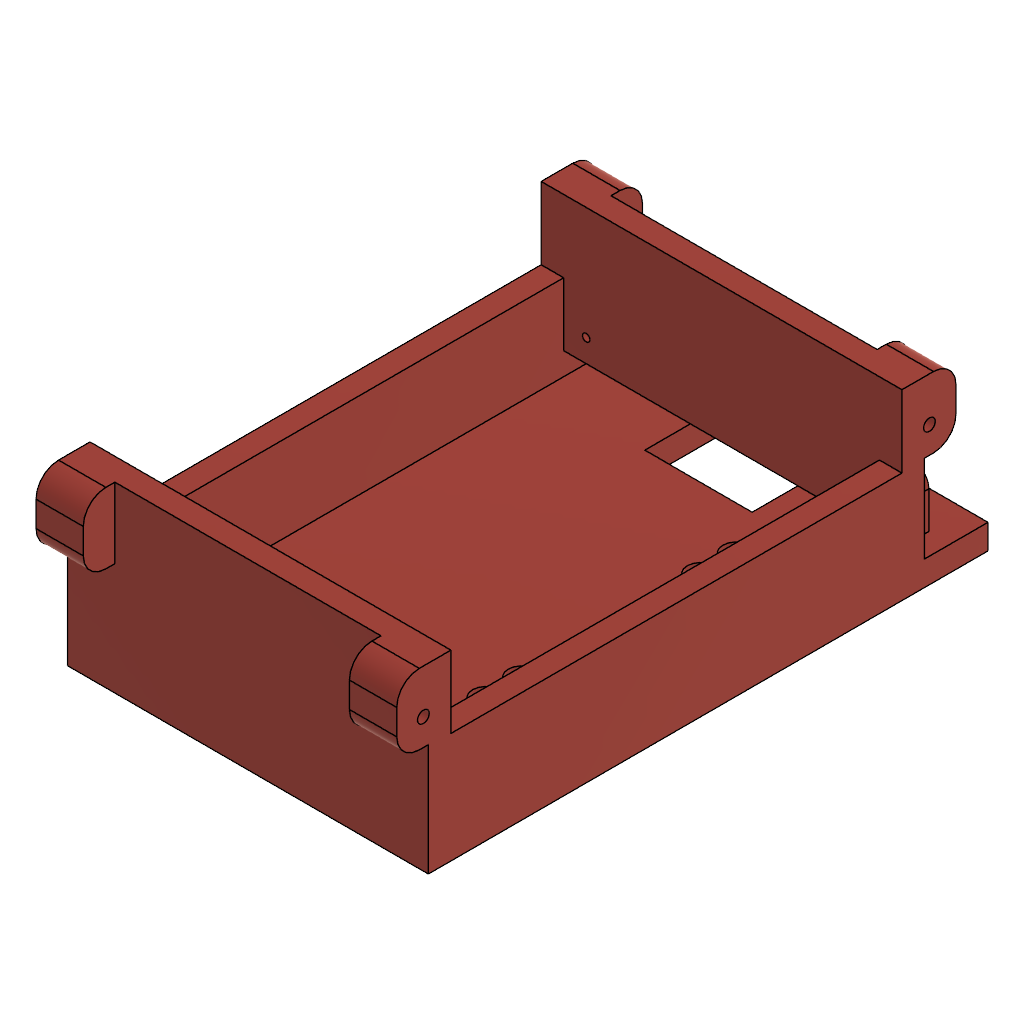
Card_Drop_Box (Autodesk Fusion 360 design; units mm, degrees)
part number: 2026-11-03-15-18-22-422
Autodesk Fusion 360 part; units mm, degrees
sketch "Çizim1" plane through (0, 0, 0) normal (0, 0, 1) x (1, 0, 0)
  line L0 (35, 50) -> (-35, 50)
  line L1 (-35, 50) -> (-35, -50)
  line L2 (-35, -50) -> (35, -50)
  line L3 (35, -50) -> (35, 50)
  line L4 (35, 50) -> (-35, -50) construction
  line L5 (-35, 50) -> (35, -50) construction
  line L6 (-40, -55) -> (40, -55)
  line L7 (40, -55) -> (40, 55)
  line L8 (40, 55) -> (-40, 55)
  line L9 (-40, 55) -> (-40, -55)
  dimension "d1" = 70
  dimension "d2" = 100
  dimension "d3" = 5
  constraint horizontal L0
  constraint perpendicular L0 L1
  constraint parallel L0 L2
  constraint parallel L1 L3
  constraint coincident L4 origin
  constraint coincident L5 origin
  measures "d1" distance of L1.end L2.end
  measures "d2" distance of L0.end L1.end
extrude "Ekstrüzyon1" add sketch "Çizim1" against normal blind 5 contours L0 L1 L2 L3 | L6 L7 L8 L9 makes body 1
extrude "Ekstrüzyon2" add sketch "Çizim1" along normal blind 35 bodies 1
sketch "Çizim2" plane through (40, 0, 0) normal (1, 0, 0) x (0, 1, 0)
  line L0 (-55, 35) -> (-55, -5)
  line L1 (-55, -5) -> (55, -5)
  line L2 (55, -5) -> (55, 35)
  line L3 (55, 35) -> (-55, 35)
  line L4 (0, 35) -> (-57, 35)
  line L5 (0, 35) -> (62, 35)
  line L6 (-56.1, 35) -> (-56.1, 25.25)
  circle A0 centre (-56.1, 25.25) radius 1.3
  circle A1 centre (-56.1, 25.25) radius 5.9
  line L7 (-62, 30) -> (-62, 25.25)
  line L8 (-62, 25.25) -> (-62, 14)
  line L9 (-56.1, 25.25) -> (-56.1, 19.35)
  line L10 (-56.1, 19.35) -> (-62, 19.35)
  line L11 (-56.1, 19.35) -> (-55, 19.35)
  arc A2 (-57, 35) -> (-62, 30) centre (-57, 30) ccw
  point P0 (-62, 35)
  dimension "d8" = 62
  dimension "d9" = 62
  dimension "d10" = 9.75
  dimension "d11" = 5.9
  dimension "d12" = 2.6
  dimension "d13" = 5
  constraint midpoint L3 L4.start
  constraint parallel L3 L4
  constraint parallel L3 L5
  constraint coincident L4 L6.start
  constraint perpendicular L4 L6
  constraint coincident L6.end A0.centre
  constraint concentric A0 A1
  constraint coincident A1 L7.end
  constraint tangent A1 L7
  constraint perpendicular L4 L7
  constraint tangent A1 L8
  constraint coincident A1 L9.end
  constraint parallel L6 L9
  constraint tangent A1 L10
  constraint coincident L0 L11.end
  constraint tangent A1 L11
  constraint coincident P0 L4
  constraint coincident P0 L7
  constraint tangent L4 A2
  constraint tangent L7 A2
  measures "d8" distance of L4.start P0
  measures "d9" distance of L4.start L5.end
  measures "d10" distance of L6.start L6.end
  measures "d11" distance of P0 L6
  measures "d12" diameter of A0
  measures "d13" radius of A2
extrude "Ekstrüzyon3" add sketch "Çizim2" against normal blind 5.5 contours L0 A1 L11 | L0 A0 A1 L9 | A1 L8 L10 | L6 A0 A1 L9 | L4 L6 A1 L7 A2 | L0 L6 A0 A1 | L0 L4 L6 A1 bodies 1
extrude "Ekstrüzyon4" cut sketch "Çizim2" against normal blind 7 contours L0 A0 bodies 1
mirror "Ayna1" about plane through (0, 0, 0) normal (0, 1, 0) of "Ekstrüzyon3", "Ekstrüzyon4"
extrude "Ekstrüzyon5" add 2 faces at (34.5, -60.4655, 24.8348) (34.5, 60.4655, 24.8348) along direction (-1, 0, 0) blind 5 on bodies 1 bodies 1
sketch "Çizim3" plane through (29.5, 0, 0) normal (-1, 0, 0) x (0, -1, 0)
  line L0 (57, 35) -> (55, 35)
  line L1 (55, 35) -> (55, 25.9428)
  arc A0 (55, 24.5572) -> (55, 25.9428) centre (56.1, 25.25) ccw
  line L2 (55, 24.5572) -> (55, 19.35)
  line L3 (55, 19.35) -> (62, 19.35)
  line L4 (62, 19.35) -> (62, 30)
  arc A1 (62, 30) -> (57, 35) centre (57, 30) ccw
  circle A2 centre (56.1, 25.25) radius 1.3
  constraint concentric A0 A2
extrude "Ekstrüzyon6" add sketch "Çizim3" against normal blind 3.5 contours A0 A2 bodies 1
mirror "Ayna2" about plane through (0, 0, 0) normal (0, 1, 0) of "Ekstrüzyon6"
mirror "Ayna3" about plane through (0, 0, 0) normal (1, 0, 0) of "Ekstrüzyon3", "Ekstrüzyon4", "Ayna1", "Ekstrüzyon5", "Ekstrüzyon6", "Ayna2"
sketch "Çizim4" plane through (-40, 0, 0) normal (-1, 0, 0) x (0, -1, 0)
  circle A0 centre (56.1, 25.25) radius 1.3
  circle A1 centre (-56.1, 25.25) radius 1.3
  line L0 (-55, 19.35) -> (-55, -5)
  line L1 (-55, -5) -> (55, -5)
  line L2 (55, -5) -> (55, 19.35)
  line L3 (62, 19.35) -> (62, 30)
  arc A2 (62, 30) -> (57, 35) centre (57, 30) ccw
  line L4 (57, 35) -> (-57, 35)
  arc A3 (-57, 35) -> (-62, 30) centre (-57, 30) ccw
  line L5 (-62, 30) -> (-62, 19.35)
  line L6 (0, 35) -> (0, 20)
  line L7 (0, 20) -> (50, 20)
  line L8 (50, 20) -> (50, 23)
  line L9 (50, 23) -> (0, 23)
  line L10 (0, 23) -> (0, 20)
  line L11 (0, 20) -> (-50, 20)
  line L12 (-50, 20) -> (-50, 23)
  line L13 (-50, 23) -> (0, 23)
  line L14 (0, 23) -> (0, 20)
  line L15 (0, 35) -> (0, 32)
  line L16 (55, 19.35) -> (62, 19.35)
  line L17 (-62, 19.35) -> (-55, 19.35)
  dimension "d34" = 15
  dimension "d35" = 50
  dimension "d36" = 3
  dimension "d37" = 3
  dimension "d40" = 50
  constraint midpoint L4 L6.start
  constraint perpendicular L4 L6
  constraint horizontal L7
  constraint vertical L8
  constraint horizontal L9
  constraint vertical L10
  constraint horizontal L11
  constraint vertical L12
  constraint horizontal L13
  constraint vertical L14
  constraint coincident L6 L15.end
  measures "d34" distance of L6.start L6.end
  measures "d35" distance of L6.end L7.end
  measures "d36" distance of L6.end L9.end
  measures "d37" distance of L6.end L9.end
  measures "d40" distance of L12.end L9.end
extrude "Ekstrüzyon7" cut sketch "Çizim4" against normal blind 80 contours L6 L7 L8 L9 L10 L14 | L6 L10 L11 L12 L13 L14 bodies 1
extrude "Ekstrüzyon8" cut 4 faces at (38.3333, -16.6667, 23) (36.6667, 33.3333, 23) (-38.3333, -33.3333, 23) (-36.6667, 16.6667, 23) along direction (0, 0, 1) blind 12 on bodies 1 bodies 1
extrude "Ekstrüzyon9" add 1 faces at (-13.3333, -18.3333, -5) along direction (0, 0, -1) blind 0.5 on bodies 1 bodies 1
sketch "Çizim5" plane through (0, 0, -5.5) normal (0, 0, -1) x (1, 0, 0)
  line L0 (-40, 55) -> (-40, -55)
  line L1 (-40, -55) -> (40, -55)
  line L2 (40, -55) -> (40, 55)
  line L3 (40, 55) -> (-40, 55)
  line L4 (-35, -50) -> (35, -50)
  line L5 (35, -50) -> (35, 50)
  line L6 (35, 50) -> (-35, 50)
  line L7 (-35, 50) -> (-35, -50)
  line L8 (0, 50) -> (0, 29.8)
  line L9 (0, 29.8) -> (-11.9, 29.8)
  line L10 (0, 29.8) -> (11.9, 29.8)
  line L11 (-11.9, 29.8) -> (11.9, 29.8)
  line L12 (11.9, 29.8) -> (11.9, 50)
  line L13 (11.9, 50) -> (-11.9, 50)
  line L14 (-11.9, 50) -> (-11.9, 29.8)
  line L15 (11.9, 50) -> (11.9, 39.9)
  line L16 (11.9, 29.8) -> (18, 29.8)
  line L17 (18, 29.8) -> (18, 20.2)
  line L18 (18, 20.2) -> (18, 12.3)
  circle A0 centre (18, 20.2) radius 1.3
  circle A1 centre (18, 12.3) radius 1.3
  dimension "d45" = -5
  dimension "d46" = 20.2
  dimension "d47" = 11.9
  dimension "d48" = 11.9
  dimension "d49" = 23.8
  dimension "d50" = 6.1
  dimension "d51" = 9.6
  dimension "d52" = 7.9
  dimension "d53" = 2.6
  dimension "d54" = 2.6
  constraint midpoint L6 L8.start
  constraint perpendicular L6 L8
  constraint perpendicular L8 L9
  constraint perpendicular L8 L10
  constraint horizontal L11
  constraint vertical L12
  constraint horizontal L13
  constraint vertical L14
  constraint midpoint L12 L15.end
  constraint perpendicular L12 L16
  constraint perpendicular L16 L17
  constraint perpendicular L11 L18
  constraint coincident L17.end L18.start
  constraint coincident L18.end A1.centre
  measures "d46" distance of L8.start L8.end
  measures "d47" distance of L8.end L9.end
  measures "d48" distance of L8.end L10.end
  measures "d49" distance of L9.end L10.end
  measures "d50" distance of L10.end L16.end
  measures "d51" distance of L16.end L17.end
  measures "d52" distance of L17.end L18.end
  measures "d53" diameter of A0
  measures "d54" diameter of A1
extrude "Ekstrüzyon10" cut sketch "Çizim5" against normal blind 5.5 contours L6 L8 L9 L11 L13 L14 | L6 L8 L10 L11 L12 L13 L15 | L17 L18 A0 | L17 L18 A0 | A1 bodies 1
sketch "Çizim6" plane through (0, 50, 0) normal (0, -1, 0) x (1, 0, 0)
  line L0 (-35, 20) -> (-35, 0)
  line L1 (-35, 0) -> (35, 0)
  line L2 (35, 0) -> (35, 20)
  line L3 (35, 20) -> (40, 20)
  line L4 (40, 20) -> (40, 35)
  line L5 (40, 35) -> (-40, 35)
  line L6 (-40, 35) -> (-40, 20)
  line L7 (-40, 20) -> (-35, 20)
  line L8 (-35, 0) -> (35, 0)
  line L9 (35, 0) -> (35, 5)
  line L10 (35, 5) -> (-35, 5)
  line L11 (-35, 5) -> (-35, 0)
  dimension "d57" = 5
  constraint horizontal L8
  constraint vertical L9
  constraint horizontal L10
  constraint vertical L11
  constraint coincident L0.end L1.start
  measures "d57" distance of L0.end L10.end
extrude "Ekstrüzyon11" cut sketch "Çizim6" against normal blind 5 contours L0 L1 L2 L8 L9 L10 L11 bodies 1
sketch "Çizim7" plane through (0, 55, 0) normal (0, 1, 0) x (-1, 0, 0)
  line L0 (35, 0) -> (-35, 0)
  line L1 (-35, 0) -> (-35, 5)
  line L2 (-35, 5) -> (35, 5)
  line L3 (35, 5) -> (35, 0)
  line L4 (29.5, 19.35) -> (29.5, 35)
  line L5 (29.5, 35) -> (-29.5, 35)
  line L6 (-29.5, 35) -> (-29.5, 19.35)
  line L7 (-29.5, 19.35) -> (-40, 19.35)
  line L8 (-40, 19.35) -> (-40, -5.5)
  line L9 (-40, -5.5) -> (40, -5.5)
  line L10 (40, -5.5) -> (40, 19.35)
  line L11 (40, 19.35) -> (29.5, 19.35)
  circle A0 centre (-30, 10) radius 1.3
  line L12 (0, 5) -> (0, 15) construction
  circle A1 centre (30, 10) radius 1.3
  dimension "d60" = 2.6
  dimension "d61" = 5
  dimension "d62" = 5
  constraint midpoint L2 L12.start
  constraint perpendicular L2 L12
  constraint symmetric A0 L12 A1
  measures "d60" diameter of A0
  measures "d61" distance of L2 A0.centre
  measures "d62" horizontal distance of L1.end A0.centre
extrude "Ekstrüzyon12" cut sketch "Çizim7" against normal blind 5 contours A0 | A1 bodies 1
extrude "Ekstrüzyon13" cut 3 faces at (-36.6667, 16.6667, 20) (38.3333, -33.3333, 20) (36.6667, 16.6667, 20) along direction (0, 0, -1) blind 1 on bodies 1 bodies 1
fillet "Kavis4" radius 5 4 edges at (-34.75, -62, 19.35) (34.75, -62, 19.35) (34.75, 62, 19.35) (-34.75, 62, 19.35) on bodies 1
sketch "Çizim8" plane through (0, 0, -5.5) normal (0, 0, -1) x (1, 0, 0)
  line L0 (11.9, 29.8) -> (-11.9, 29.8)
  line L1 (-11.9, 29.8) -> (-11.9, 50)
  line L2 (-11.9, 50) -> (11.9, 50)
  line L3 (11.9, 50) -> (11.9, 29.8)
  circle A0 centre (18, 20.2) radius 1.3
  circle A1 centre (18, 12.3) radius 1.3
  line L4 (-40, 55) -> (-40, -55)
  line L5 (-40, -55) -> (40, -55)
  line L6 (40, -55) -> (40, 55)
  line L7 (40, 55) -> (-40, 55)
  line L8 (-11.9, -65.1) -> (11.9, -65.1)
  line L9 (11.9, -65.1) -> (11.9, -44.9)
  line L10 (11.9, -44.9) -> (-11.9, -44.9)
  line L11 (-11.9, -44.9) -> (-11.9, -65.1)
  line L12 (-11.9, -65.1) -> (11.9, -44.9) construction
  line L13 (11.9, -65.1) -> (-11.9, -44.9) construction
  line L14 (15.9, -40.9) -> (-15.9, -40.9)
  line L15 (-15.9, -40.9) -> (-15.9, -69.1)
  line L16 (-15.9, -69.1) -> (15.9, -69.1)
  line L17 (15.9, -69.1) -> (15.9, -40.9)
  line L18 (40, -55) -> (-40, -55)
  line L19 (-40, -55) -> (-40, -69.1)
  line L20 (-40, -69.1) -> (40, -69.1)
  line L21 (40, -69.1) -> (40, -55)
  circle A2 centre (18, 20.2) radius 1.3
  circle A3 centre (18, 12.3) radius 1.3
  line L22 (11.9, 29.8) -> (18, 29.8)
  line L23 (18, 29.8) -> (18, 20.2)
  line L24 (11.9, -44.9) -> (11.9, -35.3)
  line L25 (11.9, -35.3) -> (18, -35.3)
  circle A4 centre (18, -35.3) radius 1.3
  line L26 (18, -35.3) -> (18, -27.4)
  circle A5 centre (18, -27.4) radius 1.3
  point P0 (0, -55)
  dimension "d69" = 23.8
  dimension "d70" = 20.2
  dimension "d71" = 4
  dimension "d72" = 14.1
  dimension "d73" = 80
  dimension "d78" = 9.6
  dimension "d79" = 6.1
  dimension "d80" = 2.6
  dimension "d81" = 7.9
  dimension "d82" = 2.6
  constraint horizontal L8
  constraint perpendicular L8 L9
  constraint parallel L8 L10
  constraint parallel L9 L11
  constraint coincident L12 P0
  constraint coincident L13 P0
  constraint midpoint L5 P0
  constraint horizontal L18
  constraint vertical L19
  constraint horizontal L20
  constraint vertical L21
  constraint coincident L5.end L6.start
  constraint concentric A0 A2
  constraint concentric A1 A3
  constraint coincident L0.start L3.end
  constraint perpendicular L3 L22
  constraint coincident A0.centre A2.centre
  constraint perpendicular L10 L24
  constraint perpendicular L24 L25
  constraint coincident L25.end A4.centre
  constraint perpendicular L25 L26
  constraint coincident L26.end A5.centre
  measures "d69" distance of L9.end L10.end
  measures "d70" distance of L8.end L9.end
  measures "d72" distance of L4.end L19.end
  measures "d73" distance of L19.end L20.end
  measures "d78" distance of L9.end L24.end
  measures "d79" distance of L24.end L25.end
  measures "d80" diameter of A4
  measures "d81" distance of L25.end L26.end
  measures "d82" diameter of A5
extrude "Ekstrüzyon14" add sketch "Çizim8" against normal blind 5.5 contours L5 L15 L18 L19 L20 | L5 L8 L9 L11 L15 L16 L17 L18 L20 | L5 L17 L18 L20 L21 bodies 1
extrude "Ekstrüzyon15" cut sketch "Çizim8" against normal blind 5.5 contours L5 L9 L10 L11 L18 bodies 1
extrude "Ekstrüzyon16" cut sketch "Çizim8" against normal blind 5.5 contours L25 A4 L26 | L25 A4 L26 | A5 bodies 1
sketch "Çizim9" plane through (0, 0, 0) normal (0, 0, 1) x (-1, 0, 0)
  circle A0 centre (-18, -35.3) radius 1.3
  circle A1 centre (-18, -27.4) radius 1.3
  line L0 (11.9, -44.9) -> (11.9, -65.1)
  line L1 (11.9, -65.1) -> (-11.9, -65.1)
  line L2 (-11.9, -65.1) -> (-11.9, -44.9)
  line L3 (-11.9, -44.9) -> (11.9, -44.9)
  line L4 (-35, -55) -> (-40, -55)
  line L5 (-40, -55) -> (-40, -69.1)
  line L6 (-40, -69.1) -> (40, -69.1)
  line L7 (40, -69.1) -> (40, -55)
  line L8 (40, -55) -> (35, -55)
  line L9 (35, -55) -> (35, 50)
  line L10 (35, 50) -> (11.9, 50)
  line L11 (11.9, 50) -> (11.9, 29.8)
  line L12 (11.9, 29.8) -> (-11.9, 29.8)
  line L13 (-11.9, 29.8) -> (-11.9, 50)
  line L14 (-11.9, 50) -> (-35, 50)
  line L15 (-35, 50) -> (-35, -55)
  circle A2 centre (-18, 20.2) radius 1.3
  circle A3 centre (-18, 12.3) radius 1.3
  circle A4 centre (-18, -35.3) radius 3
  circle A5 centre (-18, -27.4) radius 3
  circle A6 centre (-18, 12.3) radius 3
  circle A7 centre (-18, 20.2) radius 3
  dimension "d85" = 6
  dimension "d86" = 6
  dimension "d87" = 6
  dimension "d88" = 6
  constraint concentric A0 A4
  constraint concentric A1 A5
  constraint concentric A3 A6
  constraint concentric A2 A7
  measures "d85" diameter of A4
  measures "d86" diameter of A5
  measures "d87" diameter of A6
  measures "d88" diameter of A7
extrude "Ekstrüzyon17" cut sketch "Çizim9" against normal blind 2.7 contours A4 | A5 | A6 | A7 bodies 1
sketch "Çizim10" plane through (0, 55, 0) normal (0, 1, 0) x (-1, 0, 0)
  circle A0 centre (30, 10) radius 1.3
  circle A1 centre (-30, 10) radius 1.3
  line L0 (-40, 0) -> (-35, 0)
  line L1 (-35, 0) -> (-35, 5)
  line L2 (-35, 5) -> (35, 5)
  line L3 (35, 5) -> (35, 0)
  line L4 (35, 0) -> (40, 0)
  line L5 (40, 0) -> (40, 19.35)
  line L6 (40, 19.35) -> (29.5, 19.35)
  line L7 (29.5, 19.35) -> (29.5, 35)
  line L8 (29.5, 35) -> (-29.5, 35)
  line L9 (-29.5, 35) -> (-29.5, 19.35)
  line L10 (-29.5, 19.35) -> (-40, 19.35)
  line L11 (-40, 19.35) -> (-40, 0)
  circle A2 centre (-30, 10) radius 0.825
  circle A3 centre (30, 10) radius 0.825
  dimension "d91" = 1.65
  dimension "d92" = 1.65
  constraint concentric A1 A2
  constraint concentric A0 A3
  measures "d91" diameter of A2
  measures "d92" diameter of A3
extrude "Ekstrüzyon18" add sketch "Çizim10" against normal blind 5 contours A0 | A1 bodies 1
sketch "Çizim11" plane through (0, 55, 0) normal (0, 1, 0) x (-1, 0, 0)
  circle A0 centre (-30, 10) radius 0.825
  circle A1 centre (30, 10) radius 0.825
  line L0 (-40, 0) -> (-35, 0)
  line L1 (-35, 0) -> (-35, 5)
  line L2 (-35, 5) -> (35, 5)
  line L3 (35, 5) -> (35, 0)
  line L4 (35, 0) -> (40, 0)
  line L5 (40, 0) -> (40, 19.35)
  line L6 (40, 19.35) -> (29.5, 19.35)
  line L7 (29.5, 19.35) -> (29.5, 35)
  line L8 (29.5, 35) -> (-29.5, 35)
  line L9 (-29.5, 35) -> (-29.5, 19.35)
  line L10 (-29.5, 19.35) -> (-40, 19.35)
  line L11 (-40, 19.35) -> (-40, 0)
  line L12 (-35, 0) -> (-35, 0.8)
  line L13 (-35, 0.8) -> (35, 0.8)
  line L14 (-35, 0.8) -> (-36, 0.8)
  line L15 (-30, 10) -> (-30, 12.5)
  line L16 (-36, 0.8) -> (-36, 9)
  line L17 (-32.5, 12.5) -> (-30, 12.5)
  line L18 (-30, 12.5) -> (0, 12.5)
  line L19 (0, 12.5) -> (0, 0.8) construction
  line L20 (30, 12.5) -> (0, 12.5)
  line L21 (32.5, 12.5) -> (30, 12.5)
  line L22 (36, 0.8) -> (36, 9)
  line L23 (35, 0.8) -> (36, 0.8)
  arc A2 (-32.5, 12.5) -> (-36, 9) centre (-32.5, 9) ccw
  arc A3 (36, 9) -> (32.5, 12.5) centre (32.5, 9) ccw
  dimension "d95" = 0.8
  dimension "d96" = 1
  dimension "d97" = 2.5
  dimension "d98" = 3.5
  constraint coincident L0.end L1.start
  constraint perpendicular L0 L12
  constraint coincident L3 L13.end
  constraint perpendicular L3 L13
  constraint perpendicular L1 L14
  constraint coincident A0.centre L15.start
  constraint perpendicular L10 L15
  constraint perpendicular L14 L16
  constraint perpendicular L15 L17
  constraint perpendicular L15 L18
  constraint midpoint L13 L19.end
  constraint perpendicular L13 L19
  constraint symmetric L12.end L19 L13.end
  constraint symmetric L14.end L19 L22.start
  constraint symmetric L15.end L19 L20.start
  constraint symmetric L18.end L19 L20.end
  constraint tangent L16 A2
  constraint tangent L17 A2
  constraint tangent L21 A3
  constraint tangent L22 A3
  constraint equal A2 A3
  measures "d95" distance of L0.end L12.end
  measures "d96" distance of L12.end L14.end
  measures "d97" distance of A0.centre L15.end
  measures "d98" radius of A2
extrude "Ekstrüzyon19" add sketch "Çizim11" along normal blind 5 separate body contours L1 L2 L3 L14 L16 L17 L18 L20 L21 L22 L23 A2 A3 | L1 L2 L3 L13 makes body 2
equation "d8 = ( 124 / 2 ) * 1 mm"
equation "d47 = ( 23.8 / 2 ) * 1 mm"
named bodies: "Card_Drop_Box", "Card_Drop_Box_Mask"
